Autodesk Fusion 360 part; units mm, degrees
(part 2 of 3)
sketch "LowerWebY_0_Sketch" plane through (0, 0, -52) normal (0, 0, 1) x (1, 0, 0) in component "BedFrame_ElectronicsBay"
  line L0 (-98, -262.2) -> (-96, -262.2)
  line L1 (-96, -262.2) -> (-96, -255.3)
  line L2 (-96, -255.3) -> (-98, -255.3)
  line L3 (-98, -255.3) -> (-98, -262.2)
extrude "LowerWebY_0" add sketch "LowerWebY_0_Sketch" along normal blind 8 bodies 3 in component "BedFrame_ElectronicsBay"
ref_plane "WorkPlane8" through (0, 0, -52) normal (0, 0, 1) x (1, 0, 0) in component "BedFrame_ElectronicsBay"
sketch "LowerBoss_0_Sketch" plane through (0, 0, -52) normal (0, 0, 1) x (1, 0, 0) in component "BedFrame_ElectronicsBay"
  circle A0 centre (-97, -255.3) radius 2.75
extrude "LowerBoss_0" add sketch "LowerBoss_0_Sketch" along normal blind 8 bodies 3 in component "BedFrame_ElectronicsBay"
ref_plane "WorkPlane9" through (0, 0, -52.1) normal (0, 0, 1) x (1, 0, 0) in component "BedFrame_ElectronicsBay"
sketch "LowerPilot_0_Sketch" plane through (0, 0, -52.1) normal (0, 0, 1) x (1, 0, 0) in component "BedFrame_ElectronicsBay"
  circle A0 centre (-97, -255.3) radius 1.05
extrude "LowerPilot_0" cut sketch "LowerPilot_0_Sketch" along normal blind 7.1 bodies 3 in component "BedFrame_ElectronicsBay"
ref_plane "WorkPlane10" through (0, 0, -4.1) normal (0, 0, 1) x (1, 0, 0) in component "BedFrame_ElectronicsBay"
sketch "UpperClearance_1_Sketch" plane through (0, 0, -4.1) normal (0, 0, 1) x (1, 0, 0) in component "BedFrame_ElectronicsBay"
  circle A0 centre (0, -255.3) radius 1.35
extrude "UpperClearance_1" cut sketch "UpperClearance_1_Sketch" along normal blind 4.2 bodies 3 in component "BedFrame_ElectronicsBay"
ref_plane "WorkPlane11" through (0, 0, -52) normal (0, 0, 1) x (1, 0, 0) in component "BedFrame_ElectronicsBay"
sketch "LowerWebY_1_Sketch" plane through (0, 0, -52) normal (0, 0, 1) x (1, 0, 0) in component "BedFrame_ElectronicsBay"
  line L0 (-1, -262.2) -> (1, -262.2)
  line L1 (1, -262.2) -> (1, -255.3)
  line L2 (1, -255.3) -> (-1, -255.3)
  line L3 (-1, -255.3) -> (-1, -262.2)
extrude "LowerWebY_1" add sketch "LowerWebY_1_Sketch" along normal blind 8 bodies 3 in component "BedFrame_ElectronicsBay"
ref_plane "WorkPlane12" through (0, 0, -52) normal (0, 0, 1) x (1, 0, 0) in component "BedFrame_ElectronicsBay"
sketch "LowerBoss_1_Sketch" plane through (0, 0, -52) normal (0, 0, 1) x (1, 0, 0) in component "BedFrame_ElectronicsBay"
  circle A0 centre (0, -255.3) radius 2.75
extrude "LowerBoss_1" add sketch "LowerBoss_1_Sketch" along normal blind 8 bodies 3 in component "BedFrame_ElectronicsBay"
ref_plane "WorkPlane13" through (0, 0, -52.1) normal (0, 0, 1) x (1, 0, 0) in component "BedFrame_ElectronicsBay"
sketch "LowerPilot_1_Sketch" plane through (0, 0, -52.1) normal (0, 0, 1) x (1, 0, 0) in component "BedFrame_ElectronicsBay"
  circle A0 centre (0, -255.3) radius 1.05
extrude "LowerPilot_1" cut sketch "LowerPilot_1_Sketch" along normal blind 7.1 bodies 3 in component "BedFrame_ElectronicsBay"
ref_plane "WorkPlane14" through (0, 0, -4.1) normal (0, 0, 1) x (1, 0, 0) in component "BedFrame_ElectronicsBay"
sketch "UpperClearance_2_Sketch" plane through (0, 0, -4.1) normal (0, 0, 1) x (1, 0, 0) in component "BedFrame_ElectronicsBay"
  circle A0 centre (97, -255.3) radius 1.35
extrude "UpperClearance_2" cut sketch "UpperClearance_2_Sketch" along normal blind 4.2 bodies 3 in component "BedFrame_ElectronicsBay"
ref_plane "WorkPlane15" through (0, 0, -52) normal (0, 0, 1) x (1, 0, 0) in component "BedFrame_ElectronicsBay"
sketch "LowerWebX_2_Sketch" plane through (0, 0, -52) normal (0, 0, 1) x (1, 0, 0) in component "BedFrame_ElectronicsBay"
  line L0 (97, -256.3) -> (103.9, -256.3)
  line L1 (103.9, -256.3) -> (103.9, -254.3)
  line L2 (103.9, -254.3) -> (97, -254.3)
  line L3 (97, -254.3) -> (97, -256.3)
extrude "LowerWebX_2" add sketch "LowerWebX_2_Sketch" along normal blind 8 bodies 3 in component "BedFrame_ElectronicsBay"
ref_plane "WorkPlane16" through (0, 0, -52) normal (0, 0, 1) x (1, 0, 0) in component "BedFrame_ElectronicsBay"
sketch "LowerWebY_2_Sketch" plane through (0, 0, -52) normal (0, 0, 1) x (1, 0, 0) in component "BedFrame_ElectronicsBay"
  line L0 (96, -262.2) -> (98, -262.2)
  line L1 (98, -262.2) -> (98, -255.3)
  line L2 (98, -255.3) -> (96, -255.3)
  line L3 (96, -255.3) -> (96, -262.2)
extrude "LowerWebY_2" add sketch "LowerWebY_2_Sketch" along normal blind 8 bodies 3 in component "BedFrame_ElectronicsBay"
ref_plane "WorkPlane17" through (0, 0, -52) normal (0, 0, 1) x (1, 0, 0) in component "BedFrame_ElectronicsBay"
sketch "LowerBoss_2_Sketch" plane through (0, 0, -52) normal (0, 0, 1) x (1, 0, 0) in component "BedFrame_ElectronicsBay"
  circle A0 centre (97, -255.3) radius 2.75
extrude "LowerBoss_2" add sketch "LowerBoss_2_Sketch" along normal blind 8 bodies 3 in component "BedFrame_ElectronicsBay"
ref_plane "WorkPlane18" through (0, 0, -52.1) normal (0, 0, 1) x (1, 0, 0) in component "BedFrame_ElectronicsBay"
sketch "LowerPilot_2_Sketch" plane through (0, 0, -52.1) normal (0, 0, 1) x (1, 0, 0) in component "BedFrame_ElectronicsBay"
  circle A0 centre (97, -255.3) radius 1.05
extrude "LowerPilot_2" cut sketch "LowerPilot_2_Sketch" along normal blind 7.1 bodies 3 in component "BedFrame_ElectronicsBay"
ref_plane "WorkPlane19" through (0, 0, -4.1) normal (0, 0, 1) x (1, 0, 0) in component "BedFrame_ElectronicsBay"
sketch "UpperClearance_3_Sketch" plane through (0, 0, -4.1) normal (0, 0, 1) x (1, 0, 0) in component "BedFrame_ElectronicsBay"
  circle A0 centre (-97, -194.3) radius 1.35
extrude "UpperClearance_3" cut sketch "UpperClearance_3_Sketch" along normal blind 4.2 bodies 3 in component "BedFrame_ElectronicsBay"
ref_plane "WorkPlane20" through (0, 0, -52) normal (0, 0, 1) x (1, 0, 0) in component "BedFrame_ElectronicsBay"
sketch "LowerWebX_3_Sketch" plane through (0, 0, -52) normal (0, 0, 1) x (1, 0, 0) in component "BedFrame_ElectronicsBay"
  line L0 (-103.9, -195.3) -> (-97, -195.3)
  line L1 (-97, -195.3) -> (-97, -193.3)
  line L2 (-97, -193.3) -> (-103.9, -193.3)
  line L3 (-103.9, -193.3) -> (-103.9, -195.3)
extrude "LowerWebX_3" add sketch "LowerWebX_3_Sketch" along normal blind 8 bodies 3 in component "BedFrame_ElectronicsBay"
ref_plane "WorkPlane21" through (0, 0, -52) normal (0, 0, 1) x (1, 0, 0) in component "BedFrame_ElectronicsBay"
sketch "LowerBoss_3_Sketch" plane through (0, 0, -52) normal (0, 0, 1) x (1, 0, 0) in component "BedFrame_ElectronicsBay"
  circle A0 centre (-97, -194.3) radius 2.75
extrude "LowerBoss_3" add sketch "LowerBoss_3_Sketch" along normal blind 8 bodies 3 in component "BedFrame_ElectronicsBay"
ref_plane "WorkPlane22" through (0, 0, -52.1) normal (0, 0, 1) x (1, 0, 0) in component "BedFrame_ElectronicsBay"
sketch "LowerPilot_3_Sketch" plane through (0, 0, -52.1) normal (0, 0, 1) x (1, 0, 0) in component "BedFrame_ElectronicsBay"
  circle A0 centre (-97, -194.3) radius 1.05
extrude "LowerPilot_3" cut sketch "LowerPilot_3_Sketch" along normal blind 7.1 bodies 3 in component "BedFrame_ElectronicsBay"
ref_plane "WorkPlane23" through (0, 0, -4.1) normal (0, 0, 1) x (1, 0, 0) in component "BedFrame_ElectronicsBay"
sketch "UpperClearance_4_Sketch" plane through (0, 0, -4.1) normal (0, 0, 1) x (1, 0, 0) in component "BedFrame_ElectronicsBay"
  circle A0 centre (97, -194.3) radius 1.35
extrude "UpperClearance_4" cut sketch "UpperClearance_4_Sketch" along normal blind 4.2 bodies 3 in component "BedFrame_ElectronicsBay"
ref_plane "WorkPlane24" through (0, 0, -52) normal (0, 0, 1) x (1, 0, 0) in component "BedFrame_ElectronicsBay"
sketch "LowerWebX_4_Sketch" plane through (0, 0, -52) normal (0, 0, 1) x (1, 0, 0) in component "BedFrame_ElectronicsBay"
  line L0 (97, -195.3) -> (103.9, -195.3)
  line L1 (103.9, -195.3) -> (103.9, -193.3)
  line L2 (103.9, -193.3) -> (97, -193.3)
  line L3 (97, -193.3) -> (97, -195.3)
extrude "LowerWebX_4" add sketch "LowerWebX_4_Sketch" along normal blind 8 bodies 3 in component "BedFrame_ElectronicsBay"
ref_plane "WorkPlane25" through (0, 0, -52) normal (0, 0, 1) x (1, 0, 0) in component "BedFrame_ElectronicsBay"
sketch "LowerBoss_4_Sketch" plane through (0, 0, -52) normal (0, 0, 1) x (1, 0, 0) in component "BedFrame_ElectronicsBay"
  circle A0 centre (97, -194.3) radius 2.75
extrude "LowerBoss_4" add sketch "LowerBoss_4_Sketch" along normal blind 8 bodies 3 in component "BedFrame_ElectronicsBay"
ref_plane "WorkPlane26" through (0, 0, -52.1) normal (0, 0, 1) x (1, 0, 0) in component "BedFrame_ElectronicsBay"
sketch "LowerPilot_4_Sketch" plane through (0, 0, -52.1) normal (0, 0, 1) x (1, 0, 0) in component "BedFrame_ElectronicsBay"
  circle A0 centre (97, -194.3) radius 1.05
extrude "LowerPilot_4" cut sketch "LowerPilot_4_Sketch" along normal blind 7.1 bodies 3 in component "BedFrame_ElectronicsBay"
ref_plane "WorkPlane27" through (0, 0, -4.1) normal (0, 0, 1) x (1, 0, 0) in component "BedFrame_ElectronicsBay"
sketch "UpperClearance_5_Sketch" plane through (0, 0, -4.1) normal (0, 0, 1) x (1, 0, 0) in component "BedFrame_ElectronicsBay"
  circle A0 centre (-97, -133.3) radius 1.35
extrude "UpperClearance_5" cut sketch "UpperClearance_5_Sketch" along normal blind 4.2 bodies 3 in component "BedFrame_ElectronicsBay"
ref_plane "WorkPlane28" through (0, 0, -52) normal (0, 0, 1) x (1, 0, 0) in component "BedFrame_ElectronicsBay"
sketch "LowerWebX_5_Sketch" plane through (0, 0, -52) normal (0, 0, 1) x (1, 0, 0) in component "BedFrame_ElectronicsBay"
  line L0 (-103.9, -134.3) -> (-97, -134.3)
  line L1 (-97, -134.3) -> (-97, -132.3)
  line L2 (-97, -132.3) -> (-103.9, -132.3)
  line L3 (-103.9, -132.3) -> (-103.9, -134.3)
extrude "LowerWebX_5" add sketch "LowerWebX_5_Sketch" along normal blind 8 bodies 3 in component "BedFrame_ElectronicsBay"
ref_plane "WorkPlane29" through (0, 0, -52) normal (0, 0, 1) x (1, 0, 0) in component "BedFrame_ElectronicsBay"
sketch "LowerWebY_5_Sketch" plane through (0, 0, -52) normal (0, 0, 1) x (1, 0, 0) in component "BedFrame_ElectronicsBay"
  line L0 (-98, -133.3) -> (-96, -133.3)
  line L1 (-96, -133.3) -> (-96, -126.4)
  line L2 (-96, -126.4) -> (-98, -126.4)
  line L3 (-98, -126.4) -> (-98, -133.3)
extrude "LowerWebY_5" add sketch "LowerWebY_5_Sketch" along normal blind 8 bodies 3 in component "BedFrame_ElectronicsBay"
ref_plane "WorkPlane30" through (0, 0, -52) normal (0, 0, 1) x (1, 0, 0) in component "BedFrame_ElectronicsBay"
sketch "LowerBoss_5_Sketch" plane through (0, 0, -52) normal (0, 0, 1) x (1, 0, 0) in component "BedFrame_ElectronicsBay"
  circle A0 centre (-97, -133.3) radius 2.75
extrude "LowerBoss_5" add sketch "LowerBoss_5_Sketch" along normal blind 8 bodies 3 in component "BedFrame_ElectronicsBay"
ref_plane "WorkPlane31" through (0, 0, -52.1) normal (0, 0, 1) x (1, 0, 0) in component "BedFrame_ElectronicsBay"
sketch "LowerPilot_5_Sketch" plane through (0, 0, -52.1) normal (0, 0, 1) x (1, 0, 0) in component "BedFrame_ElectronicsBay"
  circle A0 centre (-97, -133.3) radius 1.05
extrude "LowerPilot_5" cut sketch "LowerPilot_5_Sketch" along normal blind 7.1 bodies 3 in component "BedFrame_ElectronicsBay"
ref_plane "WorkPlane32" through (0, 0, -4.1) normal (0, 0, 1) x (1, 0, 0) in component "BedFrame_ElectronicsBay"
sketch "UpperClearance_6_Sketch" plane through (0, 0, -4.1) normal (0, 0, 1) x (1, 0, 0) in component "BedFrame_ElectronicsBay"
  circle A0 centre (0, -133.3) radius 1.35
extrude "UpperClearance_6" cut sketch "UpperClearance_6_Sketch" along normal blind 4.2 bodies 3 in component "BedFrame_ElectronicsBay"
ref_plane "WorkPlane33" through (0, 0, -52) normal (0, 0, 1) x (1, 0, 0) in component "BedFrame_ElectronicsBay"
sketch "LowerWebY_6_Sketch" plane through (0, 0, -52) normal (0, 0, 1) x (1, 0, 0) in component "BedFrame_ElectronicsBay"
  line L0 (-1, -133.3) -> (1, -133.3)
  line L1 (1, -133.3) -> (1, -126.4)
  line L2 (1, -126.4) -> (-1, -126.4)
  line L3 (-1, -126.4) -> (-1, -133.3)
extrude "LowerWebY_6" add sketch "LowerWebY_6_Sketch" along normal blind 8 bodies 3 in component "BedFrame_ElectronicsBay"
ref_plane "WorkPlane34" through (0, 0, -52) normal (0, 0, 1) x (1, 0, 0) in component "BedFrame_ElectronicsBay"
sketch "LowerBoss_6_Sketch" plane through (0, 0, -52) normal (0, 0, 1) x (1, 0, 0) in component "BedFrame_ElectronicsBay"
  circle A0 centre (0, -133.3) radius 2.75
extrude "LowerBoss_6" add sketch "LowerBoss_6_Sketch" along normal blind 8 bodies 3 in component "BedFrame_ElectronicsBay"
ref_plane "WorkPlane35" through (0, 0, -52.1) normal (0, 0, 1) x (1, 0, 0) in component "BedFrame_ElectronicsBay"
sketch "LowerPilot_6_Sketch" plane through (0, 0, -52.1) normal (0, 0, 1) x (1, 0, 0) in component "BedFrame_ElectronicsBay"
  circle A0 centre (0, -133.3) radius 1.05
extrude "LowerPilot_6" cut sketch "LowerPilot_6_Sketch" along normal blind 7.1 bodies 3 in component "BedFrame_ElectronicsBay"
ref_plane "WorkPlane36" through (0, 0, -4.1) normal (0, 0, 1) x (1, 0, 0) in component "BedFrame_ElectronicsBay"
sketch "UpperClearance_7_Sketch" plane through (0, 0, -4.1) normal (0, 0, 1) x (1, 0, 0) in component "BedFrame_ElectronicsBay"
  circle A0 centre (97, -133.3) radius 1.35
extrude "UpperClearance_7" cut sketch "UpperClearance_7_Sketch" along normal blind 4.2 bodies 3 in component "BedFrame_ElectronicsBay"
ref_plane "WorkPlane37" through (0, 0, -52) normal (0, 0, 1) x (1, 0, 0) in component "BedFrame_ElectronicsBay"
sketch "LowerWebX_7_Sketch" plane through (0, 0, -52) normal (0, 0, 1) x (1, 0, 0) in component "BedFrame_ElectronicsBay"
  line L0 (97, -134.3) -> (103.9, -134.3)
  line L1 (103.9, -134.3) -> (103.9, -132.3)
  line L2 (103.9, -132.3) -> (97, -132.3)
  line L3 (97, -132.3) -> (97, -134.3)
extrude "LowerWebX_7" add sketch "LowerWebX_7_Sketch" along normal blind 8 bodies 3 in component "BedFrame_ElectronicsBay"
ref_plane "WorkPlane38" through (0, 0, -52) normal (0, 0, 1) x (1, 0, 0) in component "BedFrame_ElectronicsBay"
sketch "LowerWebY_7_Sketch" plane through (0, 0, -52) normal (0, 0, 1) x (1, 0, 0) in component "BedFrame_ElectronicsBay"
  line L0 (96, -133.3) -> (98, -133.3)
  line L1 (98, -133.3) -> (98, -126.4)
  line L2 (98, -126.4) -> (96, -126.4)
  line L3 (96, -126.4) -> (96, -133.3)
extrude "LowerWebY_7" add sketch "LowerWebY_7_Sketch" along normal blind 8 bodies 3 in component "BedFrame_ElectronicsBay"
ref_plane "WorkPlane39" through (0, 0, -52) normal (0, 0, 1) x (1, 0, 0) in component "BedFrame_ElectronicsBay"
sketch "LowerBoss_7_Sketch" plane through (0, 0, -52) normal (0, 0, 1) x (1, 0, 0) in component "BedFrame_ElectronicsBay"
  circle A0 centre (97, -133.3) radius 2.75
extrude "LowerBoss_7" add sketch "LowerBoss_7_Sketch" along normal blind 8 bodies 3 in component "BedFrame_ElectronicsBay"
ref_plane "WorkPlane40" through (0, 0, -52.1) normal (0, 0, 1) x (1, 0, 0) in component "BedFrame_ElectronicsBay"
sketch "LowerPilot_7_Sketch" plane through (0, 0, -52.1) normal (0, 0, 1) x (1, 0, 0) in component "BedFrame_ElectronicsBay"
  circle A0 centre (97, -133.3) radius 1.05
extrude "LowerPilot_7" cut sketch "LowerPilot_7_Sketch" along normal blind 7.1 bodies 3 in component "BedFrame_ElectronicsBay"
fillet "OuterTopEdgeSoftening''" radius 0.6 8 edges at (-102.2426, -260.5426, 0) (-104, -194.3, 0) (0, -262.3, 0) (102.2426, -260.5426, 0) (104, -194.3, 0) (102.2426, -128.0574, 0) (0, -126.3, 0) (-102.2426, -128.0574, 0) on bodies 3 in component "BedFrame_ElectronicsBay"
ref_plane "WorkPlane1" through (0, 0, -56) normal (0, 0, 1) x (1, 0, 0) in component "BedFrame_BottomPanel"
sketch "BottomPanelBlank_Sketch" plane through (0, 0, -56) normal (0, 0, 1) x (1, 0, 0) in component "BedFrame_BottomPanel"
  line L0 (-104, -262.3) -> (104, -262.3)
  line L1 (104, -262.3) -> (104, -126.3)
  line L2 (104, -126.3) -> (-104, -126.3)
  line L3 (-104, -126.3) -> (-104, -262.3)
extrude "BottomPanelBlank" add sketch "BottomPanelBlank_Sketch" along normal blind 4 separate body makes body 4 in component "BedFrame_BottomPanel"
fillet "PanelCorners" radius 6 4 edges at (-104, -126.3, -54) (104, -126.3, -54) (104, -262.3, -54) (-104, -262.3, -54) on bodies 4 in component "BedFrame_BottomPanel"
ref_plane "WorkPlane2" through (0, 0, -56.1) normal (0, 0, 1) x (1, 0, 0) in component "BedFrame_BottomPanel"
sketch "PanelClearance_0_Sketch" plane through (0, 0, -56.1) normal (0, 0, 1) x (1, 0, 0) in component "BedFrame_BottomPanel"
  circle A0 centre (-97, -255.3) radius 1.35
extrude "PanelClearance_0" cut sketch "PanelClearance_0_Sketch" along normal blind 4.2 bodies 4 in component "BedFrame_BottomPanel"
ref_plane "WorkPlane3" through (0, 0, -56.1) normal (0, 0, 1) x (1, 0, 0) in component "BedFrame_BottomPanel"
sketch "PanelClearance_1_Sketch" plane through (0, 0, -56.1) normal (0, 0, 1) x (1, 0, 0) in component "BedFrame_BottomPanel"
  circle A0 centre (0, -255.3) radius 1.35
extrude "PanelClearance_1" cut sketch "PanelClearance_1_Sketch" along normal blind 4.2 bodies 4 in component "BedFrame_BottomPanel"
ref_plane "WorkPlane4" through (0, 0, -56.1) normal (0, 0, 1) x (1, 0, 0) in component "BedFrame_BottomPanel"
sketch "PanelClearance_2_Sketch" plane through (0, 0, -56.1) normal (0, 0, 1) x (1, 0, 0) in component "BedFrame_BottomPanel"
  circle A0 centre (97, -255.3) radius 1.35
extrude "PanelClearance_2" cut sketch "PanelClearance_2_Sketch" along normal blind 4.2 bodies 4 in component "BedFrame_BottomPanel"
ref_plane "WorkPlane5" through (0, 0, -56.1) normal (0, 0, 1) x (1, 0, 0) in component "BedFrame_BottomPanel"
sketch "PanelClearance_3_Sketch" plane through (0, 0, -56.1) normal (0, 0, 1) x (1, 0, 0) in component "BedFrame_BottomPanel"
  circle A0 centre (-97, -194.3) radius 1.35
extrude "PanelClearance_3" cut sketch "PanelClearance_3_Sketch" along normal blind 4.2 bodies 4 in component "BedFrame_BottomPanel"
ref_plane "WorkPlane6" through (0, 0, -56.1) normal (0, 0, 1) x (1, 0, 0) in component "BedFrame_BottomPanel"
sketch "PanelClearance_4_Sketch" plane through (0, 0, -56.1) normal (0, 0, 1) x (1, 0, 0) in component "BedFrame_BottomPanel"
  circle A0 centre (97, -194.3) radius 1.35
extrude "PanelClearance_4" cut sketch "PanelClearance_4_Sketch" along normal blind 4.2 bodies 4 in component "BedFrame_BottomPanel"
ref_plane "WorkPlane7" through (0, 0, -56.1) normal (0, 0, 1) x (1, 0, 0) in component "BedFrame_BottomPanel"
sketch "PanelClearance_5_Sketch" plane through (0, 0, -56.1) normal (0, 0, 1) x (1, 0, 0) in component "BedFrame_BottomPanel"
  circle A0 centre (-97, -133.3) radius 1.35
extrude "PanelClearance_5" cut sketch "PanelClearance_5_Sketch" along normal blind 4.2 bodies 4 in component "BedFrame_BottomPanel"
ref_plane "WorkPlane8" through (0, 0, -56.1) normal (0, 0, 1) x (1, 0, 0) in component "BedFrame_BottomPanel"
sketch "PanelClearance_6_Sketch" plane through (0, 0, -56.1) normal (0, 0, 1) x (1, 0, 0) in component "BedFrame_BottomPanel"
  circle A0 centre (0, -133.3) radius 1.35
extrude "PanelClearance_6" cut sketch "PanelClearance_6_Sketch" along normal blind 4.2 bodies 4 in component "BedFrame_BottomPanel"
ref_plane "WorkPlane9" through (0, 0, -56.1) normal (0, 0, 1) x (1, 0, 0) in component "BedFrame_BottomPanel"
sketch "PanelClearance_7_Sketch" plane through (0, 0, -56.1) normal (0, 0, 1) x (1, 0, 0) in component "BedFrame_BottomPanel"
  circle A0 centre (97, -133.3) radius 1.35
extrude "PanelClearance_7" cut sketch "PanelClearance_7_Sketch" along normal blind 4.2 bodies 4 in component "BedFrame_BottomPanel"
ref_plane "WorkPlane10" through (0, 0, -56.1) normal (0, 0, 1) x (1, 0, 0) in component "BedFrame_BottomPanel"
sketch "Vent_0_Sketch" plane through (0, 0, -56.1) normal (0, 0, 1) x (1, 0, 0) in component "BedFrame_BottomPanel"
  line L0 (-29.5, -203.3) -> (-26.5, -203.3)
  line L1 (-26.5, -203.3) -> (-26.5, -185.3)
  line L2 (-26.5, -185.3) -> (-29.5, -185.3)
  line L3 (-29.5, -185.3) -> (-29.5, -203.3)
extrude "Vent_0" cut sketch "Vent_0_Sketch" along normal blind 4.2 bodies 4 in component "BedFrame_BottomPanel"
ref_plane "WorkPlane11" through (0, 0, -56.1) normal (0, 0, 1) x (1, 0, 0) in component "BedFrame_BottomPanel"
sketch "Vent_1_Sketch" plane through (0, 0, -56.1) normal (0, 0, 1) x (1, 0, 0) in component "BedFrame_BottomPanel"
  line L0 (-21.5, -203.3) -> (-18.5, -203.3)
  line L1 (-18.5, -203.3) -> (-18.5, -185.3)
  line L2 (-18.5, -185.3) -> (-21.5, -185.3)
  line L3 (-21.5, -185.3) -> (-21.5, -203.3)
extrude "Vent_1" cut sketch "Vent_1_Sketch" along normal blind 4.2 bodies 4 in component "BedFrame_BottomPanel"
ref_plane "WorkPlane12" through (0, 0, -56.1) normal (0, 0, 1) x (1, 0, 0) in component "BedFrame_BottomPanel"
sketch "Vent_2_Sketch" plane through (0, 0, -56.1) normal (0, 0, 1) x (1, 0, 0) in component "BedFrame_BottomPanel"
  line L0 (-13.5, -203.3) -> (-10.5, -203.3)
  line L1 (-10.5, -203.3) -> (-10.5, -185.3)
  line L2 (-10.5, -185.3) -> (-13.5, -185.3)
  line L3 (-13.5, -185.3) -> (-13.5, -203.3)
extrude "Vent_2" cut sketch "Vent_2_Sketch" along normal blind 4.2 bodies 4 in component "BedFrame_BottomPanel"
ref_plane "WorkPlane13" through (0, 0, -56.1) normal (0, 0, 1) x (1, 0, 0) in component "BedFrame_BottomPanel"
sketch "Vent_3_Sketch" plane through (0, 0, -56.1) normal (0, 0, 1) x (1, 0, 0) in component "BedFrame_BottomPanel"
  line L0 (-5.5, -203.3) -> (-2.5, -203.3)
  line L1 (-2.5, -203.3) -> (-2.5, -185.3)
  line L2 (-2.5, -185.3) -> (-5.5, -185.3)
  line L3 (-5.5, -185.3) -> (-5.5, -203.3)
extrude "Vent_3" cut sketch "Vent_3_Sketch" along normal blind 4.2 bodies 4 in component "BedFrame_BottomPanel"
ref_plane "WorkPlane14" through (0, 0, -56.1) normal (0, 0, 1) x (1, 0, 0) in component "BedFrame_BottomPanel"
sketch "Vent_4_Sketch" plane through (0, 0, -56.1) normal (0, 0, 1) x (1, 0, 0) in component "BedFrame_BottomPanel"
  line L0 (2.5, -203.3) -> (5.5, -203.3)
  line L1 (5.5, -203.3) -> (5.5, -185.3)
  line L2 (5.5, -185.3) -> (2.5, -185.3)
  line L3 (2.5, -185.3) -> (2.5, -203.3)
extrude "Vent_4" cut sketch "Vent_4_Sketch" along normal blind 4.2 bodies 4 in component "BedFrame_BottomPanel"
ref_plane "WorkPlane15" through (0, 0, -56.1) normal (0, 0, 1) x (1, 0, 0) in component "BedFrame_BottomPanel"
sketch "Vent_5_Sketch" plane through (0, 0, -56.1) normal (0, 0, 1) x (1, 0, 0) in component "BedFrame_BottomPanel"
  line L0 (10.5, -203.3) -> (13.5, -203.3)
  line L1 (13.5, -203.3) -> (13.5, -185.3)
  line L2 (13.5, -185.3) -> (10.5, -185.3)
  line L3 (10.5, -185.3) -> (10.5, -203.3)
extrude "Vent_5" cut sketch "Vent_5_Sketch" along normal blind 4.2 bodies 4 in component "BedFrame_BottomPanel"
ref_plane "WorkPlane16" through (0, 0, -56.1) normal (0, 0, 1) x (1, 0, 0) in component "BedFrame_BottomPanel"
sketch "Vent_6_Sketch" plane through (0, 0, -56.1) normal (0, 0, 1) x (1, 0, 0) in component "BedFrame_BottomPanel"
  line L0 (18.5, -203.3) -> (21.5, -203.3)
  line L1 (21.5, -203.3) -> (21.5, -185.3)
  line L2 (21.5, -185.3) -> (18.5, -185.3)
  line L3 (18.5, -185.3) -> (18.5, -203.3)
extrude "Vent_6" cut sketch "Vent_6_Sketch" along normal blind 4.2 bodies 4 in component "BedFrame_BottomPanel"
ref_plane "WorkPlane17" through (0, 0, -56.1) normal (0, 0, 1) x (1, 0, 0) in component "BedFrame_BottomPanel"
sketch "Vent_7_Sketch" plane through (0, 0, -56.1) normal (0, 0, 1) x (1, 0, 0) in component "BedFrame_BottomPanel"
  line L0 (26.5, -203.3) -> (29.5, -203.3)
  line L1 (29.5, -203.3) -> (29.5, -185.3)
  line L2 (29.5, -185.3) -> (26.5, -185.3)
  line L3 (26.5, -185.3) -> (26.5, -203.3)
extrude "Vent_7" cut sketch "Vent_7_Sketch" along normal blind 4.2 bodies 4 in component "BedFrame_BottomPanel"
fillet "OuterTopEdgeSoftening'''" radius 0.6 8 edges at (-102.2426, -260.5426, -52) (-104, -194.3, -52) (0, -262.3, -52) (102.2426, -260.5426, -52) (104, -194.3, -52) (102.2426, -128.0574, -52) (0, -126.3, -52) (-102.2426, -128.0574, -52) on bodies 4 in component "BedFrame_BottomPanel"
ref_plane "WorkPlane1" through (0, 0, 2) normal (0, 0, 1) x (1, 0, 0) in component "Reference_Valve_A1"
sketch "Envelope_Sketch" plane through (0, 0, 2) normal (0, 0, 1) x (1, 0, 0) in component "Reference_Valve_A1"
  line L0 (-42, -173.3) -> (-30, -173.3)
  line L1 (-30, -173.3) -> (-30, -151.3)
  line L2 (-30, -151.3) -> (-42, -151.3)
  line L3 (-42, -151.3) -> (-42, -173.3)
extrude "Envelope" add sketch "Envelope_Sketch" along normal blind 30 separate body makes body 5 in component "Reference_Valve_A1"
ref_plane "WorkPlane1" through (0, 0, 2) normal (0, 0, 1) x (1, 0, 0) in component "Reference_Valve_B1"
sketch "Envelope_Sketch (2)" plane through (0, 0, 2) normal (0, 0, 1) x (1, 0, 0) in component "Reference_Valve_B1"
  line L0 (-18, -173.3) -> (-6, -173.3)
  line L1 (-6, -173.3) -> (-6, -151.3)
  line L2 (-6, -151.3) -> (-18, -151.3)
  line L3 (-18, -151.3) -> (-18, -173.3)
extrude "Envelope'" add sketch "Envelope_Sketch (2)" along normal blind 30 separate body makes body 6 in component "Reference_Valve_B1"
ref_plane "WorkPlane1" through (0, 0, 2) normal (0, 0, 1) x (1, 0, 0) in component "Reference_Valve_C1"
sketch "Envelope_Sketch (3)" plane through (0, 0, 2) normal (0, 0, 1) x (1, 0, 0) in component "Reference_Valve_C1"
  line L0 (6, -173.3) -> (18, -173.3)
  line L1 (18, -173.3) -> (18, -151.3)
  line L2 (18, -151.3) -> (6, -151.3)
  line L3 (6, -151.3) -> (6, -173.3)
extrude "Envelope''" add sketch "Envelope_Sketch (3)" along normal blind 30 separate body makes body 7 in component "Reference_Valve_C1"
ref_plane "WorkPlane1" through (0, 0, 2) normal (0, 0, 1) x (1, 0, 0) in component "Reference_Valve_A2"
sketch "Envelope_Sketch (4)" plane through (0, 0, 2) normal (0, 0, 1) x (1, 0, 0) in component "Reference_Valve_A2"
  line L0 (30, -173.3) -> (42, -173.3)
  line L1 (42, -173.3) -> (42, -151.3)
  line L2 (42, -151.3) -> (30, -151.3)
  line L3 (30, -151.3) -> (30, -173.3)
extrude "Envelope'''" add sketch "Envelope_Sketch (4)" along normal blind 30 separate body makes body 8 in component "Reference_Valve_A2"
ref_plane "WorkPlane1" through (0, 0, 2) normal (0, 0, 1) x (1, 0, 0) in component "Reference_Valve_B2"
sketch "Envelope_Sketch (5)" plane through (0, 0, 2) normal (0, 0, 1) x (1, 0, 0) in component "Reference_Valve_B2"
  line L0 (-42, -205.3) -> (-30, -205.3)
  line L1 (-30, -205.3) -> (-30, -183.3)
  line L2 (-30, -183.3) -> (-42, -183.3)
  line L3 (-42, -183.3) -> (-42, -205.3)
extrude "Envelope''''" add sketch "Envelope_Sketch (5)" along normal blind 30 separate body makes body 9 in component "Reference_Valve_B2"
ref_plane "WorkPlane1" through (0, 0, 2) normal (0, 0, 1) x (1, 0, 0) in component "Reference_Valve_C2"
sketch "Envelope_Sketch (6)" plane through (0, 0, 2) normal (0, 0, 1) x (1, 0, 0) in component "Reference_Valve_C2"
  line L0 (-18, -205.3) -> (-6, -205.3)
  line L1 (-6, -205.3) -> (-6, -183.3)
  line L2 (-6, -183.3) -> (-18, -183.3)
  line L3 (-18, -183.3) -> (-18, -205.3)
extrude "Envelope'''''" add sketch "Envelope_Sketch (6)" along normal blind 30 separate body makes body 10 in component "Reference_Valve_C2"
ref_plane "WorkPlane1" through (0, 0, 2) normal (0, 0, 1) x (1, 0, 0) in component "Reference_Valve_A3"
sketch "Envelope_Sketch (7)" plane through (0, 0, 2) normal (0, 0, 1) x (1, 0, 0) in component "Reference_Valve_A3"
  line L0 (6, -205.3) -> (18, -205.3)
  line L1 (18, -205.3) -> (18, -183.3)
  line L2 (18, -183.3) -> (6, -183.3)
  line L3 (6, -183.3) -> (6, -205.3)
extrude "Envelope''''''" add sketch "Envelope_Sketch (7)" along normal blind 30 separate body makes body 11 in component "Reference_Valve_A3"
ref_plane "WorkPlane1" through (0, 0, 2) normal (0, 0, 1) x (1, 0, 0) in component "Reference_Valve_B3"
sketch "Envelope_Sketch (8)" plane through (0, 0, 2) normal (0, 0, 1) x (1, 0, 0) in component "Reference_Valve_B3"
  line L0 (30, -205.3) -> (42, -205.3)
  line L1 (42, -205.3) -> (42, -183.3)
  line L2 (42, -183.3) -> (30, -183.3)
  line L3 (30, -183.3) -> (30, -205.3)
extrude "Envelope'''''''" add sketch "Envelope_Sketch (8)" along normal blind 30 separate body makes body 12 in component "Reference_Valve_B3"
ref_plane "WorkPlane1" through (0, 0, 2) normal (0, 0, 1) x (1, 0, 0) in component "Reference_Valve_C3"
sketch "Envelope_Sketch (9)" plane through (0, 0, 2) normal (0, 0, 1) x (1, 0, 0) in component "Reference_Valve_C3"
  line L0 (-42, -237.3) -> (-30, -237.3)
  line L1 (-30, -237.3) -> (-30, -215.3)
  line L2 (-30, -215.3) -> (-42, -215.3)
  line L3 (-42, -215.3) -> (-42, -237.3)
extrude "Envelope''''''''" add sketch "Envelope_Sketch (9)" along normal blind 30 separate body makes body 13 in component "Reference_Valve_C3"
ref_plane "WorkPlane1" through (0, 0, 2) normal (0, 0, 1) x (1, 0, 0) in component "Reference_Valve_A4"
sketch "Envelope_Sketch (10)" plane through (0, 0, 2) normal (0, 0, 1) x (1, 0, 0) in component "Reference_Valve_A4"
  line L0 (-18, -237.3) -> (-6, -237.3)
  line L1 (-6, -237.3) -> (-6, -215.3)
  line L2 (-6, -215.3) -> (-18, -215.3)
  line L3 (-18, -215.3) -> (-18, -237.3)
extrude "Envelope'''''''''" add sketch "Envelope_Sketch (10)" along normal blind 30 separate body makes body 14 in component "Reference_Valve_A4"
ref_plane "WorkPlane1" through (0, 0, 2) normal (0, 0, 1) x (1, 0, 0) in component "Reference_Valve_B4"
sketch "Envelope_Sketch (11)" plane through (0, 0, 2) normal (0, 0, 1) x (1, 0, 0) in component "Reference_Valve_B4"
  line L0 (6, -237.3) -> (18, -237.3)
  line L1 (18, -237.3) -> (18, -215.3)
  line L2 (18, -215.3) -> (6, -215.3)
  line L3 (6, -215.3) -> (6, -237.3)
extrude "Envelope''''''''''" add sketch "Envelope_Sketch (11)" along normal blind 30 separate body makes body 15 in component "Reference_Valve_B4"
ref_plane "WorkPlane1" through (0, 0, 2) normal (0, 0, 1) x (1, 0, 0) in component "Reference_Valve_C4"
sketch "Envelope_Sketch (12)" plane through (0, 0, 2) normal (0, 0, 1) x (1, 0, 0) in component "Reference_Valve_C4"
  line L0 (30, -237.3) -> (42, -237.3)
  line L1 (42, -237.3) -> (42, -215.3)
  line L2 (42, -215.3) -> (30, -215.3)
  line L3 (30, -215.3) -> (30, -237.3)
extrude "Envelope'''''''''''" add sketch "Envelope_Sketch (12)" along normal blind 30 separate body makes body 16 in component "Reference_Valve_C4"
ref_plane "WorkPlane1" through (0, -123, 0) normal (0, 1, 0) x (0, 0, 1) in component "Reference_ScrewCell_0_0"
sketch "Sketch1" plane through (0, -123, 0) normal (0, 1, 0) x (1, 0, 0) in component "Reference_ScrewCell_0_0"
  circle A0 centre (-84, -26) radius 1.25
extrude "Shank" add sketch "Sketch1" against normal blind 10 separate body makes body 17 in component "Reference_ScrewCell_0_0"
ref_plane "WorkPlane2" through (0, -123, 0) normal (0, 1, 0) x (0, 0, 1) in component "Reference_ScrewCell_0_0"
sketch "Sketch2" plane through (0, -123, 0) normal (0, 1, 0) x (1, 0, 0) in component "Reference_ScrewCell_0_0"
  circle A0 centre (-84, -26) radius 2.5
extrude "Head" add sketch "Sketch2" along normal blind 2 bodies 17 in component "Reference_ScrewCell_0_0"
ref_plane "WorkPlane1" through (0, -123, 0) normal (0, 1, 0) x (0, 0, 1) in component "Reference_ScrewCell_0_1"
sketch "Sketch1 (2)" plane through (0, -123, 0) normal (0, 1, 0) x (1, 0, 0) in component "Reference_ScrewCell_0_1"
  circle A0 centre (-22, -26) radius 1.25
extrude "Shank'" add sketch "Sketch1 (2)" against normal blind 10 separate body makes body 18 in component "Reference_ScrewCell_0_1"
ref_plane "WorkPlane2" through (0, -123, 0) normal (0, 1, 0) x (0, 0, 1) in component "Reference_ScrewCell_0_1"
sketch "Sketch2 (2)" plane through (0, -123, 0) normal (0, 1, 0) x (1, 0, 0) in component "Reference_ScrewCell_0_1"
  circle A0 centre (-22, -26) radius 2.5
extrude "Head'" add sketch "Sketch2 (2)" along normal blind 2 bodies 18 in component "Reference_ScrewCell_0_1"
ref_plane "WorkPlane1" through (0, -123, 0) normal (0, 1, 0) x (0, 0, 1) in component "Reference_ScrewCell_0_2"
sketch "Sketch1 (3)" plane through (0, -123, 0) normal (0, 1, 0) x (1, 0, 0) in component "Reference_ScrewCell_0_2"
  circle A0 centre (22, -26) radius 1.25
extrude "Shank''" add sketch "Sketch1 (3)" against normal blind 10 separate body makes body 19 in component "Reference_ScrewCell_0_2"
ref_plane "WorkPlane2" through (0, -123, 0) normal (0, 1, 0) x (0, 0, 1) in component "Reference_ScrewCell_0_2"
sketch "Sketch2 (3)" plane through (0, -123, 0) normal (0, 1, 0) x (1, 0, 0) in component "Reference_ScrewCell_0_2"
  circle A0 centre (22, -26) radius 2.5
extrude "Head''" add sketch "Sketch2 (3)" along normal blind 2 bodies 19 in component "Reference_ScrewCell_0_2"
ref_plane "WorkPlane1" through (0, -123, 0) normal (0, 1, 0) x (0, 0, 1) in component "Reference_ScrewCell_0_3"
sketch "Sketch1 (4)" plane through (0, -123, 0) normal (0, 1, 0) x (1, 0, 0) in component "Reference_ScrewCell_0_3"
  circle A0 centre (84, -26) radius 1.25
extrude "Shank'''" add sketch "Sketch1 (4)" against normal blind 10 separate body makes body 20 in component "Reference_ScrewCell_0_3"
ref_plane "WorkPlane2" through (0, -123, 0) normal (0, 1, 0) x (0, 0, 1) in component "Reference_ScrewCell_0_3"
sketch "Sketch2 (4)" plane through (0, -123, 0) normal (0, 1, 0) x (1, 0, 0) in component "Reference_ScrewCell_0_3"
  circle A0 centre (84, -26) radius 2.5
extrude "Head'''" add sketch "Sketch2 (4)" along normal blind 2 bodies 20 in component "Reference_ScrewCell_0_3"
ref_plane "WorkPlane1" through (0, 0, -4) normal (0, 0, 1) x (1, 0, 0) in component "Reference_ScrewRim_0"
sketch "Sketch1 (5)" plane through (0, 0, -4) normal (0, 0, 1) x (1, 0, 0) in component "Reference_ScrewRim_0"
  circle A0 centre (-97, -255.3) radius 1.25
extrude "Shank''''" add sketch "Sketch1 (5)" along normal blind 10 separate body makes body 21 in component "Reference_ScrewRim_0"
ref_plane "WorkPlane2" through (0, 0, -4) normal (0, 0, 1) x (1, 0, 0) in component "Reference_ScrewRim_0"
sketch "Sketch2 (5)" plane through (0, 0, -4) normal (0, 0, 1) x (1, 0, 0) in component "Reference_ScrewRim_0"
  circle A0 centre (-97, -255.3) radius 2.5
extrude "Head''''" add sketch "Sketch2 (5)" against normal blind 2 bodies 21 in component "Reference_ScrewRim_0"
ref_plane "WorkPlane1" through (0, 0, -4) normal (0, 0, 1) x (1, 0, 0) in component "Reference_ScrewRim_1"
sketch "Sketch1 (6)" plane through (0, 0, -4) normal (0, 0, 1) x (1, 0, 0) in component "Reference_ScrewRim_1"
  circle A0 centre (0, -255.3) radius 1.25
extrude "Shank'''''" add sketch "Sketch1 (6)" along normal blind 10 separate body makes body 22 in component "Reference_ScrewRim_1"
ref_plane "WorkPlane2" through (0, 0, -4) normal (0, 0, 1) x (1, 0, 0) in component "Reference_ScrewRim_1"
sketch "Sketch2 (6)" plane through (0, 0, -4) normal (0, 0, 1) x (1, 0, 0) in component "Reference_ScrewRim_1"
  circle A0 centre (0, -255.3) radius 2.5
extrude "Head'''''" add sketch "Sketch2 (6)" against normal blind 2 bodies 22 in component "Reference_ScrewRim_1"
ref_plane "WorkPlane1" through (0, 0, -4) normal (0, 0, 1) x (1, 0, 0) in component "Reference_ScrewRim_2"
sketch "Sketch1 (7)" plane through (0, 0, -4) normal (0, 0, 1) x (1, 0, 0) in component "Reference_ScrewRim_2"
  circle A0 centre (97, -255.3) radius 1.25
extrude "Shank''''''" add sketch "Sketch1 (7)" along normal blind 10 separate body makes body 23 in component "Reference_ScrewRim_2"
ref_plane "WorkPlane2" through (0, 0, -4) normal (0, 0, 1) x (1, 0, 0) in component "Reference_ScrewRim_2"
sketch "Sketch2 (7)" plane through (0, 0, -4) normal (0, 0, 1) x (1, 0, 0) in component "Reference_ScrewRim_2"
  circle A0 centre (97, -255.3) radius 2.5
extrude "Head''''''" add sketch "Sketch2 (7)" against normal blind 2 bodies 23 in component "Reference_ScrewRim_2"
ref_plane "WorkPlane1" through (0, 0, -4) normal (0, 0, 1) x (1, 0, 0) in component "Reference_ScrewRim_3"
sketch "Sketch1 (8)" plane through (0, 0, -4) normal (0, 0, 1) x (1, 0, 0) in component "Reference_ScrewRim_3"
  circle A0 centre (-97, -194.3) radius 1.25
extrude "Shank'''''''" add sketch "Sketch1 (8)" along normal blind 10 separate body makes body 24 in component "Reference_ScrewRim_3"
ref_plane "WorkPlane2" through (0, 0, -4) normal (0, 0, 1) x (1, 0, 0) in component "Reference_ScrewRim_3"
sketch "Sketch2 (8)" plane through (0, 0, -4) normal (0, 0, 1) x (1, 0, 0) in component "Reference_ScrewRim_3"
  circle A0 centre (-97, -194.3) radius 2.5
extrude "Head'''''''" add sketch "Sketch2 (8)" against normal blind 2 bodies 24 in component "Reference_ScrewRim_3"
ref_plane "WorkPlane1" through (0, 0, -4) normal (0, 0, 1) x (1, 0, 0) in component "Reference_ScrewRim_4"
sketch "Sketch1 (9)" plane through (0, 0, -4) normal (0, 0, 1) x (1, 0, 0) in component "Reference_ScrewRim_4"
  circle A0 centre (97, -194.3) radius 1.25
extrude "Shank''''''''" add sketch "Sketch1 (9)" along normal blind 10 separate body makes body 25 in component "Reference_ScrewRim_4"
ref_plane "WorkPlane2" through (0, 0, -4) normal (0, 0, 1) x (1, 0, 0) in component "Reference_ScrewRim_4"
sketch "Sketch2 (9)" plane through (0, 0, -4) normal (0, 0, 1) x (1, 0, 0) in component "Reference_ScrewRim_4"
  circle A0 centre (97, -194.3) radius 2.5
extrude "Head''''''''" add sketch "Sketch2 (9)" against normal blind 2 bodies 25 in component "Reference_ScrewRim_4"
ref_plane "WorkPlane1" through (0, 0, -4) normal (0, 0, 1) x (1, 0, 0) in component "Reference_ScrewRim_5"
sketch "Sketch1 (10)" plane through (0, 0, -4) normal (0, 0, 1) x (1, 0, 0) in component "Reference_ScrewRim_5"
  circle A0 centre (-97, -133.3) radius 1.25
extrude "Shank'''''''''" add sketch "Sketch1 (10)" along normal blind 10 separate body makes body 26 in component "Reference_ScrewRim_5"
ref_plane "WorkPlane2" through (0, 0, -4) normal (0, 0, 1) x (1, 0, 0) in component "Reference_ScrewRim_5"
sketch "Sketch2 (10)" plane through (0, 0, -4) normal (0, 0, 1) x (1, 0, 0) in component "Reference_ScrewRim_5"
  circle A0 centre (-97, -133.3) radius 2.5
extrude "Head'''''''''" add sketch "Sketch2 (10)" against normal blind 2 bodies 26 in component "Reference_ScrewRim_5"
ref_plane "WorkPlane1" through (0, 0, -4) normal (0, 0, 1) x (1, 0, 0) in component "Reference_ScrewRim_6"
sketch "Sketch1 (11)" plane through (0, 0, -4) normal (0, 0, 1) x (1, 0, 0) in component "Reference_ScrewRim_6"
  circle A0 centre (0, -133.3) radius 1.25
extrude "Shank''''''''''" add sketch "Sketch1 (11)" along normal blind 10 separate body makes body 27 in component "Reference_ScrewRim_6"
ref_plane "WorkPlane2" through (0, 0, -4) normal (0, 0, 1) x (1, 0, 0) in component "Reference_ScrewRim_6"
sketch "Sketch2 (11)" plane through (0, 0, -4) normal (0, 0, 1) x (1, 0, 0) in component "Reference_ScrewRim_6"
  circle A0 centre (0, -133.3) radius 2.5
extrude "Head''''''''''" add sketch "Sketch2 (11)" against normal blind 2 bodies 27 in component "Reference_ScrewRim_6"
ref_plane "WorkPlane1" through (0, 0, -4) normal (0, 0, 1) x (1, 0, 0) in component "Reference_ScrewRim_7"
sketch "Sketch1 (12)" plane through (0, 0, -4) normal (0, 0, 1) x (1, 0, 0) in component "Reference_ScrewRim_7"
  circle A0 centre (97, -133.3) radius 1.25
extrude "Shank'''''''''''" add sketch "Sketch1 (12)" along normal blind 10 separate body makes body 28 in component "Reference_ScrewRim_7"
ref_plane "WorkPlane2" through (0, 0, -4) normal (0, 0, 1) x (1, 0, 0) in component "Reference_ScrewRim_7"
sketch "Sketch2 (12)" plane through (0, 0, -4) normal (0, 0, 1) x (1, 0, 0) in component "Reference_ScrewRim_7"
  circle A0 centre (97, -133.3) radius 2.5
extrude "Head'''''''''''" add sketch "Sketch2 (12)" against normal blind 2 bodies 28 in component "Reference_ScrewRim_7"
ref_plane "WorkPlane1" through (0, 0, -56) normal (0, 0, 1) x (1, 0, 0) in component "Reference_ScrewPanel_0"
sketch "Sketch1 (13)" plane through (0, 0, -56) normal (0, 0, 1) x (1, 0, 0) in component "Reference_ScrewPanel_0"
  circle A0 centre (-97, -255.3) radius 1.25
extrude "Shank''''''''''''" add sketch "Sketch1 (13)" along normal blind 10 separate body makes body 29 in component "Reference_ScrewPanel_0"
ref_plane "WorkPlane2" through (0, 0, -56) normal (0, 0, 1) x (1, 0, 0) in component "Reference_ScrewPanel_0"
sketch "Sketch2 (13)" plane through (0, 0, -56) normal (0, 0, 1) x (1, 0, 0) in component "Reference_ScrewPanel_0"
  circle A0 centre (-97, -255.3) radius 2.5
extrude "Head''''''''''''" add sketch "Sketch2 (13)" against normal blind 2 bodies 29 in component "Reference_ScrewPanel_0"
ref_plane "WorkPlane1" through (0, 0, -56) normal (0, 0, 1) x (1, 0, 0) in component "Reference_ScrewPanel_1"
sketch "Sketch1 (14)" plane through (0, 0, -56) normal (0, 0, 1) x (1, 0, 0) in component "Reference_ScrewPanel_1"
  circle A0 centre (0, -255.3) radius 1.25
extrude "Shank'''''''''''''" add sketch "Sketch1 (14)" along normal blind 10 separate body makes body 30 in component "Reference_ScrewPanel_1"
ref_plane "WorkPlane2" through (0, 0, -56) normal (0, 0, 1) x (1, 0, 0) in component "Reference_ScrewPanel_1"
sketch "Sketch2 (14)" plane through (0, 0, -56) normal (0, 0, 1) x (1, 0, 0) in component "Reference_ScrewPanel_1"
  circle A0 centre (0, -255.3) radius 2.5
extrude "Head'''''''''''''" add sketch "Sketch2 (14)" against normal blind 2 bodies 30 in component "Reference_ScrewPanel_1"
ref_plane "WorkPlane1" through (0, 0, -56) normal (0, 0, 1) x (1, 0, 0) in component "Reference_ScrewPanel_2"
sketch "Sketch1 (15)" plane through (0, 0, -56) normal (0, 0, 1) x (1, 0, 0) in component "Reference_ScrewPanel_2"
  circle A0 centre (97, -255.3) radius 1.25
extrude "Shank''''''''''''''" add sketch "Sketch1 (15)" along normal blind 10 separate body makes body 31 in component "Reference_ScrewPanel_2"
ref_plane "WorkPlane2" through (0, 0, -56) normal (0, 0, 1) x (1, 0, 0) in component "Reference_ScrewPanel_2"
sketch "Sketch2 (15)" plane through (0, 0, -56) normal (0, 0, 1) x (1, 0, 0) in component "Reference_ScrewPanel_2"
  circle A0 centre (97, -255.3) radius 2.5
extrude "Head''''''''''''''" add sketch "Sketch2 (15)" against normal blind 2 bodies 31 in component "Reference_ScrewPanel_2"
ref_plane "WorkPlane1" through (0, 0, -56) normal (0, 0, 1) x (1, 0, 0) in component "Reference_ScrewPanel_3"
sketch "Sketch1 (16)" plane through (0, 0, -56) normal (0, 0, 1) x (1, 0, 0) in component "Reference_ScrewPanel_3"
  circle A0 centre (-97, -194.3) radius 1.25
extrude "Shank'''''''''''''''" add sketch "Sketch1 (16)" along normal blind 10 separate body makes body 32 in component "Reference_ScrewPanel_3"
ref_plane "WorkPlane2" through (0, 0, -56) normal (0, 0, 1) x (1, 0, 0) in component "Reference_ScrewPanel_3"
sketch "Sketch2 (16)" plane through (0, 0, -56) normal (0, 0, 1) x (1, 0, 0) in component "Reference_ScrewPanel_3"
  circle A0 centre (-97, -194.3) radius 2.5
extrude "Head'''''''''''''''" add sketch "Sketch2 (16)" against normal blind 2 bodies 32 in component "Reference_ScrewPanel_3"
ref_plane "WorkPlane1" through (0, 0, -56) normal (0, 0, 1) x (1, 0, 0) in component "Reference_ScrewPanel_4"
sketch "Sketch1 (17)" plane through (0, 0, -56) normal (0, 0, 1) x (1, 0, 0) in component "Reference_ScrewPanel_4"
  circle A0 centre (97, -194.3) radius 1.25
extrude "Shank''''''''''''''''" add sketch "Sketch1 (17)" along normal blind 10 separate body makes body 33 in component "Reference_ScrewPanel_4"
ref_plane "WorkPlane2" through (0, 0, -56) normal (0, 0, 1) x (1, 0, 0) in component "Reference_ScrewPanel_4"
sketch "Sketch2 (17)" plane through (0, 0, -56) normal (0, 0, 1) x (1, 0, 0) in component "Reference_ScrewPanel_4"
  circle A0 centre (97, -194.3) radius 2.5
extrude "Head''''''''''''''''" add sketch "Sketch2 (17)" against normal blind 2 bodies 33 in component "Reference_ScrewPanel_4"
ref_plane "WorkPlane1" through (0, 0, -56) normal (0, 0, 1) x (1, 0, 0) in component "Reference_ScrewPanel_5"
sketch "Sketch1 (18)" plane through (0, 0, -56) normal (0, 0, 1) x (1, 0, 0) in component "Reference_ScrewPanel_5"
  circle A0 centre (-97, -133.3) radius 1.25
extrude "Shank'''''''''''''''''" add sketch "Sketch1 (18)" along normal blind 10 separate body makes body 34 in component "Reference_ScrewPanel_5"
ref_plane "WorkPlane2" through (0, 0, -56) normal (0, 0, 1) x (1, 0, 0) in component "Reference_ScrewPanel_5"
sketch "Sketch2 (18)" plane through (0, 0, -56) normal (0, 0, 1) x (1, 0, 0) in component "Reference_ScrewPanel_5"
  circle A0 centre (-97, -133.3) radius 2.5
extrude "Head'''''''''''''''''" add sketch "Sketch2 (18)" against normal blind 2 bodies 34 in component "Reference_ScrewPanel_5"
ref_plane "WorkPlane1" through (0, 0, -56) normal (0, 0, 1) x (1, 0, 0) in component "Reference_ScrewPanel_6"
sketch "Sketch1 (19)" plane through (0, 0, -56) normal (0, 0, 1) x (1, 0, 0) in component "Reference_ScrewPanel_6"
  circle A0 centre (0, -133.3) radius 1.25
extrude "Shank''''''''''''''''''" add sketch "Sketch1 (19)" along normal blind 10 separate body makes body 35 in component "Reference_ScrewPanel_6"
ref_plane "WorkPlane2" through (0, 0, -56) normal (0, 0, 1) x (1, 0, 0) in component "Reference_ScrewPanel_6"
sketch "Sketch2 (19)" plane through (0, 0, -56) normal (0, 0, 1) x (1, 0, 0) in component "Reference_ScrewPanel_6"
  circle A0 centre (0, -133.3) radius 2.5
extrude "Head''''''''''''''''''" add sketch "Sketch2 (19)" against normal blind 2 bodies 35 in component "Reference_ScrewPanel_6"
ref_plane "WorkPlane1" through (0, 0, -56) normal (0, 0, 1) x (1, 0, 0) in component "Reference_ScrewPanel_7"
sketch "Sketch1 (20)" plane through (0, 0, -56) normal (0, 0, 1) x (1, 0, 0) in component "Reference_ScrewPanel_7"
  circle A0 centre (97, -133.3) radius 1.25
extrude "Shank'''''''''''''''''''" add sketch "Sketch1 (20)" along normal blind 10 separate body makes body 36 in component "Reference_ScrewPanel_7"
ref_plane "WorkPlane2" through (0, 0, -56) normal (0, 0, 1) x (1, 0, 0) in component "Reference_ScrewPanel_7"
sketch "Sketch2 (20)" plane through (0, 0, -56) normal (0, 0, 1) x (1, 0, 0) in component "Reference_ScrewPanel_7"
  circle A0 centre (97, -133.3) radius 2.5
extrude "Head'''''''''''''''''''" add sketch "Sketch2 (20)" against normal blind 2 bodies 36 in component "Reference_ScrewPanel_7"
component "Assembly_Assembled" placed x (1, 0, 0) y (0, 1, 0) z (0, 0, 1) at (0, 0, 0)
component "Inspection_Exploded" placed x (1, 0, 0) y (0, 1, 0) z (0, 0, 1) at (0, 0, 0)
component "BedFrame_CellDeck" placed x (1, 0, 0) y (0, 1, 0) z (0, 0, 1) at (0, 0, 0) in component "Assembly_Assembled"
component "BedFrame_ServiceDeck" placed x (1, 0, 0) y (0, 1, 0) z (0, 0, 1) at (0, 0, 0) in component "Assembly_Assembled"
component "BedFrame_ElectronicsBay" placed x (1, 0, 0) y (0, 1, 0) z (0, 0, 1) at (0, 0, 0) in component "Assembly_Assembled"
component "BedFrame_BottomPanel" placed x (1, 0, 0) y (0, 1, 0) z (0, 0, 1) at (0, 0, 0) in component "Assembly_Assembled"
component "Reference_ValveEnvelopes_UNMEASURED" placed x (1, 0, 0) y (0, 1, 0) z (0, 0, 1) at (0, 0, 0) in component "Assembly_Assembled"
component "Reference_CellJointScrews" placed x (1, 0, 0) y (0, 1, 0) z (0, 0, 1) at (0, 0, 0) in component "Assembly_Assembled"
component "Reference_RimScrews" placed x (1, 0, 0) y (0, 1, 0) z (0, 0, 1) at (0, 0, 0) in component "Assembly_Assembled"
component "Reference_PanelScrews" placed x (1, 0, 0) y (0, 1, 0) z (0, 0, 1) at (0, 0, 0) in component "Assembly_Assembled"
component "Reference_Valve_A1" placed x (1, 0, 0) y (0, 1, 0) z (0, 0, 1) at (0, 0, 0) in component "Reference_ValveEnvelopes_UNMEASURED"
component "Reference_Valve_B1" placed x (1, 0, 0) y (0, 1, 0) z (0, 0, 1) at (0, 0, 0) in component "Reference_ValveEnvelopes_UNMEASURED"
component "Reference_Valve_C1" placed x (1, 0, 0) y (0, 1, 0) z (0, 0, 1) at (0, 0, 0) in component "Reference_ValveEnvelopes_UNMEASURED"
component "Reference_Valve_A2" placed x (1, 0, 0) y (0, 1, 0) z (0, 0, 1) at (0, 0, 0) in component "Reference_ValveEnvelopes_UNMEASURED"
component "Reference_Valve_B2" placed x (1, 0, 0) y (0, 1, 0) z (0, 0, 1) at (0, 0, 0) in component "Reference_ValveEnvelopes_UNMEASURED"
component "Reference_Valve_C2" placed x (1, 0, 0) y (0, 1, 0) z (0, 0, 1) at (0, 0, 0) in component "Reference_ValveEnvelopes_UNMEASURED"
component "Reference_Valve_A3" placed x (1, 0, 0) y (0, 1, 0) z (0, 0, 1) at (0, 0, 0) in component "Reference_ValveEnvelopes_UNMEASURED"
component "Reference_Valve_B3" placed x (1, 0, 0) y (0, 1, 0) z (0, 0, 1) at (0, 0, 0) in component "Reference_ValveEnvelopes_UNMEASURED"
component "Reference_Valve_C3" placed x (1, 0, 0) y (0, 1, 0) z (0, 0, 1) at (0, 0, 0) in component "Reference_ValveEnvelopes_UNMEASURED"
component "Reference_Valve_A4" placed x (1, 0, 0) y (0, 1, 0) z (0, 0, 1) at (0, 0, 0) in component "Reference_ValveEnvelopes_UNMEASURED"
component "Reference_Valve_B4" placed x (1, 0, 0) y (0, 1, 0) z (0, 0, 1) at (0, 0, 0) in component "Reference_ValveEnvelopes_UNMEASURED"
component "Reference_Valve_C4" placed x (1, 0, 0) y (0, 1, 0) z (0, 0, 1) at (0, 0, 0) in component "Reference_ValveEnvelopes_UNMEASURED"
component "BedFrame_CellDeck" placed x (1, 0, 0) y (0, 1, 0) z (0, 0, 1) at (0, 0, 0) in component "Inspection_Exploded"
component "BedFrame_ServiceDeck" placed x (1, 0, 0) y (0, 1, 0) z (0, 0, 1) at (0, 0, 0) in component "Inspection_Exploded"
component "BedFrame_ElectronicsBay" placed x (1, 0, 0) y (0, 1, 0) z (0, 0, 1) at (0, 0, 0) in component "Inspection_Exploded"
component "BedFrame_BottomPanel" placed x (1, 0, 0) y (0, 1, 0) z (0, 0, 1) at (0, 0, 0) in component "Inspection_Exploded"
component "Reference_ValveEnvelopes_UNMEASURED" placed x (1, 0, 0) y (0, 1, 0) z (0, 0, 1) at (0, 0, 0) in component "Inspection_Exploded"
component "Reference_CellJointScrews" placed x (1, 0, 0) y (0, 1, 0) z (0, 0, 1) at (0, 0, 0) in component "Inspection_Exploded"
component "Reference_RimScrews" placed x (1, 0, 0) y (0, 1, 0) z (0, 0, 1) at (0, 0, 0) in component "Inspection_Exploded"
component "Reference_PanelScrews" placed x (1, 0, 0) y (0, 1, 0) z (0, 0, 1) at (0, 0, 0) in component "Inspection_Exploded"
component "Reference_ScrewCell_0_0" placed x (1, 0, 0) y (0, 1, 0) z (0, 0, 1) at (0, 0, 0) in component "Reference_CellJointScrews"